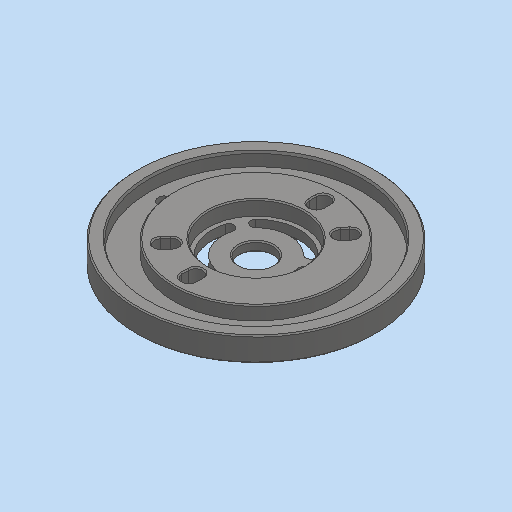
# Autodesk Inventor part: MM0948AN100_G01_197
Saved by Autodesk Inventor 2023.3 (Build 273359000, 359)
## iProperties
Part Number: MM0948AN100_G01_197
Material: 1.2099 X5CrS12
Description: =<RBPARTNOTITLE2>
Document SubType Name: Modeling
Designer: ric7an
Mass: 522.707 g
Surface Area: 263.379 cm^2
Volume: 66.5869 cm^3
Density: 7.85 g/cm^3
Appearance: Stahl - rostfrei AnP
RBDOCUMENTTYPE: DRF
RBDOCUMENTVERSION: 00
RBDRAWINGMAINSCALE: 1:1
RBDRAWINGMISSINGSPEC: --
RBDRAWINGVOLUME: --
RBGBEDGESIN1: +0,5
RBGBEDGESIN2: +0,2
RBGBEDGESOUT1: -0,3
RBGBEDGESOUT2: -0,1
RBMATERIAL: =<Material>
RBMATMEETS: --
RBMATNO: =<Part Number>
RBPARTMADEOF: Ø105 x 19,5 (FM)
RBPARTNO: SIEHE MNR
RBPARTNOTITLE1: manufactured part
RBPARTNOTITLE2: Anfertigungsteil
RBPARTSAFETYINDICATOR: --
RBSURFACE: --
RBSURFACE2: --
RBZEDGESNORM: ISO13715:2002-06
RBZGENDIMCLASS: m
RBZGENDIMNORM: ISO 2768-1:1989-11
RBZGENGEOCLASS: H
RBZGENGEONORM: ISO 2768-2:1989-11
RBZSURFACENORM: ISO13D2:2002-02
RBZTOLERANCENORM: ISO 14405-1:2010-12
AnP_Material: =<Material>
AnP_TemplVers: 20190222
AnP_Kategorie: 1
MaxAbmaße: 19,502 x 105 x 105 (FM)
Author: ric7an
Keywords: =<RBPARTMADEOF>
Comments: =<RBSURFACE2>
Revision Number: 01
Autodesk Inventor part; units mm, degrees
ref_plane "YZ Plane" through (0, 0, 0) normal (1, 0, 0) x (0, 1, 0)
ref_plane "XZ Plane" through (0, 0, 0) normal (0, 1, 0) x (-1, 0, 0)
ref_plane "XY Plane" through (0, 0, 0) normal (0, 0, 1) x (1, 0, 0)
sketch "Skizze1" plane through (0, 0, 0) normal (0, 0, 1) x (1, 0, 0)
  circle A0 centre (0, 0) radius 52.5
  dimension "d0" = 105
  constraints: 1 centre point, 1 coincident
  measures "d0" diameter of A0
extrude "Extrusion1" add sketch "Skizze1" along normal blind 22
sketch "Skizze7" plane through (0, 0, 0) normal (1, 0, 0) x (0, 1, 0)
  line L0 (52.5, 22) -> (-52.5, 22) projected
  line L1 (-52.5, 0) -> (52.5, 0) projected
  line L2 (0, 26.9323) -> (0, -16.1154)
  line L3 (-47, 22) -> (-47, 19.8)
  line L4 (-47, 19.8) -> (-44.8061, 16)
  line L5 (-44.8061, 16) -> (-36, 16)
  line L6 (-36, 16) -> (-36, 22)
  line L7 (-47, 22) -> (-36, 22)
  line L8 (52.5, 22) -> (-52.5, 22) projected
  line L9 (-52.5, 0) -> (52.5, 0) projected
  line L10 (-47, 19.8) -> (-44.8061, 19.8)
  line L11 (-44.8061, 19.8) -> (-44.8061, 16)
  line L12 (-44.8061, 16) -> (-47, 16)
  line L13 (-47, 16) -> (-47, 19.8)
  point P0 (0, 0)
  point P1 (0, 0)
  dimension "d88" = 11
  dimension "d91" = 60
  dimension "d92" = 94
  dimension "d101" = 2.2
  dimension "d102" = 6
  constraints: 20 end point, 3 perpendicular, 2 parallel, 2 vertical, 1 collinear, 1 horizontal, 1 midpoint, 1 point on line
  measures "d88" distance between parallel lines of L6 L3
  measures "d91" angle of L5 L4
  measures "d92" diameter of L3 L2
  measures "d101" distance of L3.start L3.end
  measures "d102" distance between parallel lines of L5 L7
revolve "Umdrehung1" cut sketch "Skizze7" angle 360 about axis through (0, 0, 26.9323) along (0, 0, -1)
sketch "Skizze11" plane through (0, 0, 22) normal (0, 0, 1) x (1, 0, 0)
  line L0 (0, 73.5) -> (0, -73.5) projected
  line L1 (-73.5, 0) -> (73.5, 0) projected
  point P0 (0, 0)
  point P1 (0, 0)
  constraints: 2 midpoint, 1 coincident
hole "Bohrung3" at (0, 0, 22) direction (0, 0, -1) diameter 15 end through all
sketch "Skizze13" plane through (0, 0, 0) normal (0, 0, -1) x (-1, 0, 0)
  circle A0 centre (0, 0) radius 22
  circle A1 centre (0, 0) radius 34
  circle A2 centre (0, 0) radius 52.5 projected
  dimension "d93" = 44
  dimension "d96" = 68
  constraints: 2 centre point, 2 coincident
  measures "d93" diameter of A0
  measures "d96" diameter of A1
extrude "Extrusion7" cut sketch "Skizze13" against normal blind 11.5
chamfer "Fase5" distance 0.5 angle 45 3 edges at (22, 0, 0) (34, 0, 0) (-52.5, 0, 11.5)
chamfer "Fase8" distance 0.5 angle 45 2 edges at (0, 7.5, 22) (0, 7.5, 11.5)
sketch "Skizze16" plane through (0, 0, 22) normal (0, 0, 1) x (1, 0, 0)
  line L0 (0, 73.5) -> (0, -73.5) projected
  line L1 (0, 29.5) -> (0, 26.5) construction
  line L2 (-3.05, 29.5) -> (-3.05, 26.5)
  line L3 (3.05, 26.5) -> (3.05, 29.5)
  arc A0 (3.05, 29.5) -> (-3.05, 29.5) centre (0, 29.5) ccw
  arc A1 (-3.05, 26.5) -> (3.05, 26.5) centre (0, 26.5) ccw
  line L4 (0, -26.5) -> (0, -29.5) construction
  line L5 (-3.05, -26.5) -> (-3.05, -29.5)
  line L6 (3.05, -29.5) -> (3.05, -26.5)
  arc A2 (3.05, -26.5) -> (-3.05, -26.5) centre (0, -26.5) ccw
  arc A3 (-3.05, -29.5) -> (3.05, -29.5) centre (0, -29.5) ccw
  line L7 (18.9622, 22.5983) -> (17.0339, 20.3002) construction
  line L8 (16.6258, 24.5588) -> (14.6974, 22.2607)
  line L9 (19.3703, 18.3397) -> (21.2987, 20.6378)
  arc A4 (21.2987, 20.6378) -> (16.6258, 24.5588) centre (18.9622, 22.5983) ccw
  arc A5 (14.6974, 22.2607) -> (19.3703, 18.3397) centre (17.0339, 20.3002) ccw
  line L10 (-17.0339, -20.3002) -> (-18.9622, -22.5983) construction
  line L11 (-19.3703, -18.3397) -> (-21.2987, -20.6378)
  line L12 (-16.6258, -24.5588) -> (-14.6974, -22.2607)
  arc A6 (-14.6974, -22.2607) -> (-19.3703, -18.3397) centre (-17.0339, -20.3002) ccw
  arc A7 (-21.2987, -20.6378) -> (-16.6258, -24.5588) centre (-18.9622, -22.5983) ccw
  line L13 (-17.9981, -21.4492) -> (17.9981, 21.4492) construction
  circle A8 centre (0, 0) radius 28 construction
  point P0 (0, 0)
  point P1 (0, 28)
  point P2 (0, -28)
  dimension "d138" = 3
  dimension "d139" = 6.1
  dimension "d140" = 3
  dimension "d141" = 6.1
  dimension "d142" = 28
  dimension "d143" = 28
  dimension "d155" = 40
  dimension "d158" = 3
  dimension "d159" = 3
  dimension "d188" = 6.1
  dimension "d189" = 6.1
  constraints: 34 end point, 19 point on circle, 16 tangent, 9 centre point, 5 midpoint, 5 point on line, 4 parallel, 2 collinear, 1 coincident
  measures "d138" distance of L1.end L1.start
  measures "d139" distance between parallel lines of L3 L2
  measures "d140" distance of L6.start L6.end
  measures "d141" distance between parallel lines of L6 L5
  measures "d142" distance of point (0, 0) A8.start
  measures "d143" distance of point (0, 0) point (0, -28)
  measures "d155" angle of L7 L0
  measures "d158" distance of L9.start L9.end
  measures "d159" distance of L12.start L12.end
  measures "d188" distance between parallel lines of L9 L8
  measures "d189" distance between parallel lines of L12 L11
extrude "Extrusion9" cut sketch "Skizze16" against normal through all
sketch "Skizze17" plane through (0, 0, 22) normal (0, 0, 1) x (1, 0, 0)
  line L0 (0, 74.6) -> (0, -80.1) projected
  line L1 (-73.5, 0) -> (73.5, 0) projected
  arc A0 (-16.4207, 4.3999) -> (-4.3999, -16.4207) centre (0, 0) ccw construction
  arc A1 (-18.5941, 4.9823) -> (-4.9823, -18.5941) centre (0, 0) ccw
  arc A2 (-14.2474, 3.8176) -> (-3.8176, -14.2474) centre (0, 0) ccw
  arc A3 (-14.2474, 3.8176) -> (-18.5941, 4.9823) centre (-16.4207, 4.3999) ccw
  arc A4 (-4.9823, -18.5941) -> (-3.8176, -14.2474) centre (-4.3999, -16.4207) ccw
  point P0 (0, 0)
  point P1 (0, -58)
  dimension "d146" = 90
  dimension "d147" = 15
  dimension "d148" = 17
  dimension "d149" = 2.25
  dimension "d193" = 58
  constraints: 10 point on circle, 5 centre point, 4 tangent, 1 coincident, 1 point on line
  measures "d148" radius of A0
  measures "d149" radius of A3
  measures "d193" distance from line of L1 point (0, -58)
extrude "Extrusion10" cut sketch "Skizze17" against normal through all
pattern_circular "Runde Anordnung1" count 3 over 360 about axis through (0, 0, -10) along (0, 0, 1) of "Extrusion10"
sketch "Skizze18" plane through (0, 0, 22) normal (0, 0, 1) x (1, 0, 0)
  circle A0 centre (0, 0) radius 21
  point P0 (0, 0)
  dimension "d160" = 42
  constraints: 1 centre point, 1 coincident
  measures "d160" diameter of A0
extrude "Extrusion11" cut sketch "Skizze18" against normal blind 6.4
sketch "Skizze20" plane through (0, 0, 16) normal (0, 0, 1) x (1, 0, 0)
  circle A0 centre (-40, 0) radius 3
  line L0 (-38.25, -3.5) -> (-38.25, 3.5) construction
  line L1 (-39, -3.5) -> (-39, 3.5)
  line L2 (-37.5, 3.5) -> (-37.5, -3.5)
  arc A1 (-39, -3.5) -> (-37.5, -3.5) centre (-38.25, -3.5) ccw
  arc A2 (-37.5, 3.5) -> (-39, 3.5) centre (-38.25, 3.5) ccw
  line L3 (-73.5, 0) -> (73.5, 0) projected
  circle A3 centre (-30.6418, 25.7115) radius 3
  line L4 (-31.551, 21.9055) -> (-27.0514, 27.2678) construction
  line L5 (-32.1255, 22.3876) -> (-27.626, 27.7499)
  line L6 (-26.4769, 26.7857) -> (-30.9764, 21.4234)
  arc A4 (-32.1255, 22.3876) -> (-30.9764, 21.4234) centre (-31.551, 21.9055) ccw
  arc A5 (-26.4769, 26.7857) -> (-27.626, 27.7499) centre (-27.0514, 27.2678) ccw
  line L7 (0, 0) -> (-30.6418, 25.7115) construction
  arc A6 (-14.6974, -22.2607) -> (-19.3703, -18.3397) centre (-17.0339, -20.3002) ccw projected
  arc A7 (14.6974, 22.2607) -> (19.3703, 18.3397) centre (17.0339, 20.3002) ccw projected
  line L8 (-17.0339, -20.3002) -> (17.0339, 20.3002) construction
  point P0 (-38.25, 0)
  point P1 (-39, -2.8284)
  point P2 (-39, 2.8284)
  point P3 (-29.3012, 24.5866)
  point P4 (-28.0577, 27.2354)
  point P5 (-31.6938, 22.902)
  dimension "d171" = 6
  dimension "d174" = 1.5
  dimension "d176" = 7
  dimension "d177" = 2.5
  dimension "d178" = 40
  dimension "d194" = 6
  dimension "d195" = 2.5
  dimension "d197" = 7
  dimension "d198" = 1.5
  dimension "d199" = 40
  constraints: 20 end point, 8 point on circle, 8 tangent, 6 centre point, 3 point on line, 2 midpoint, 2 parallel, 2 perpendicular, 1 vertical
  measures "d171" diameter of A0
  measures "d174" distance between parallel lines of L2 L1
  measures "d176" distance of L0.start L0.end
  measures "d177" distance from line of L2 A0.centre
  measures "d178" distance of L7.start A0.centre
  measures "d194" diameter of A3
  measures "d195" distance from line of L6 L7.end
  measures "d197" distance of L4.start L4.end
  measures "d198" distance between parallel lines of L6 L5
  measures "d199" distance of L7.start L7.end
extrude "Extrusion12" cut sketch "Skizze20" against normal blind 2.5 contours L2 L3 L1 A0 | A0 L1 A2 L2 | L2 A1 L1 A0 | A0 L1 L3 L2 | L1 L3 A0 | A0 L3 L1 | A3 L6 L5 | A3 L5 A5 L6 | L5 A3 | A3 L6 A4 L5
sketch "Skizze21" plane through (0, 0, 13.5) normal (0, 0, 1) x (1, 0, 0)
  arc A0 (-39, 2.8284) -> (-39, -2.8284) centre (-40, 0) ccw projected
  arc A1 (-28.0577, 27.2354) -> (-31.6938, 22.902) centre (-30.6418, 25.7115) ccw projected
  point P0 (0, 0)
  point P1 (-40, 0)
  constraints: 2 coincident
hole "Bohrung7" at (-40, 0, 13.5) at (-30.6418, 25.7115, 13.5) direction (0, 0, -1) diameter 3.4 end through all clearance for "Inbusschraube ISO 4762  versenkt" size "M3" standard "ISO"
chamfer "Fase10" distance 0.5 angle 45 36 edges at (-52.5, 0, 22) (0, 36, 22) (-21, 0, 22) (0, 7.5, 15.6) (-20.3345, -19.4887, 22) (-15.0734, -17.9637, 22) (-15.6616, -23.4097, 22) (-20.9227, -24.9347, 22) (0, -32.55, 22) (-3.05, -28, 22) (0, -23.45, 22) (3.05, -28, 22) (15.6616, 23.4097, 22) (20.9227, 24.9347, 22) (20.3345, 19.4887, 22) (15.0734, 17.9637, 22) (3.05, 28, 22) (0, 23.45, 22) (-3.05, 28, 22) (0, 32.55, 22) (-20.3345, -19.4887, 0) (-20.9227, -24.9347, 0) (-15.6616, -23.4097, 0) (-15.0734, -17.9637, 0) (-3.05, -28, 0) (0, -32.55, 0) (3.05, -28, 0) (0, -23.45, 0) (3.05, 28, 0) (0, 32.55, 0) (-3.05, 28, 0) (0, 23.45, 0) (15.6616, 23.4097, 0) (15.0734, 17.9637, 0) (20.3345, 19.4887, 0) (20.9227, 24.9347, 0)
chamfer "Fase11" distance 1 angle 25 1 edges at (0, 47, 22) measured on face at (32.9522, 33.5135, 20)
sketch "Skizze22" plane through (0, 0, 0) normal (0, 0, -1) x (-1, 0, 0)
  circle A0 centre (0, 0) radius 34 construction
  circle A1 centre (0, 0) radius 22 construction
  line L0 (73.5, 0) -> (-73.5, 0) construction
  circle A2 centre (0, 0) radius 32
  circle A3 centre (0, 0) radius 24
  line L1 (0, 0) -> (-29.0018, 13.5238)
  line L2 (0, 0) -> (-13.5238, -29.0018)
  arc A4 (-3.05, -29.5) -> (3.05, -29.5) centre (0, -29.5) ccw projected
  arc A5 (16.6258, -24.5588) -> (21.2987, -20.6378) centre (18.9622, -22.5983) ccw projected
  line L3 (0, -29.5) -> (0, 0)
  line L4 (0, 0) -> (18.9622, -22.5983)
  line L5 (0, 0) -> (-30.0702, -10.9446)
  line L6 (0, 0) -> (13.5238, 29.0018)
  line L7 (0, 0) -> (29.0018, -13.5238)
  point P0 (-10.1428, -21.7514)
  point P1 (-21.7514, 10.1428)
  point P2 (21.7514, -10.1428)
  point P3 (10.1428, 21.7514)
  dimension "d203" = 2
  dimension "d204" = 2
  dimension "d205" = 8
  dimension "d206" = 90
  dimension "d210" = 40
  dimension "d211" = 20
  constraints: 14 end point, 5 point on circle, 2 centre point, 2 coincident, 1 collinear, 1 perpendicular, 1 point on line, 1 symmetric about line
  measures "d203" radial gap between concentric circles of A2 A0
  measures "d204" radial gap between concentric circles of A1 A3
  measures "d205" radial gap between concentric circles of A3 A2
  measures "d206" angle of L1 L2
  measures "d210" angle of L4 L3
  measures "d211" angle of L0 L5
extrude "Extrusion13" [suppressed]
fillet "Rundung3" [suppressed]
sketch "Skizze23" plane through (0, 0, 0) normal (0, 0, -1) x (-1, 0, 0)
  circle A0 centre (0, 0) radius 34 projected
  circle A1 centre (0, 0) radius 22 projected
extrude "Extrusion14" cut sketch "Skizze23" against normal blind 8.5
chamfer "Fase12" distance 0.5 angle 45 2 edges at (34, 0, 8.5) (22, 0, 8.5)
equation "\"d140\" = d138"
equation "\"d141\" = d139"
equation "\"d143\" = d142"
equation "\"d158\" = d138"
equation "\"d159\" = d138"
equation "\"d188\" = d139"
equation "\"d189\" = d139"
